Autodesk Inventor part; units mm, degrees
(part 3 of 3)
sketch "Sketch11" plane through (0, 7, 0) normal (0, 1, 0) x (1, 0, 0)
  circle A0 centre (-224.5, -119.5) radius 26.5 projected
  circle A1 centre (-224.5, -56.5) radius 26.5 projected
  circle A2 centre (-224.5, 11.5) radius 26.5 projected
  circle A3 centre (-224.5, 74.5) radius 26.5 projected
  circle A4 centre (-161.5, 74.5) radius 26.5 projected
  circle A5 centre (-161.5, 11.5) radius 26.5 projected
  circle A6 centre (-161.5, -56.5) radius 26.5 projected
  circle A7 centre (-161.5, -119.5) radius 26.5 projected
  circle A8 centre (-98.5, -119.5) radius 26.5 projected
  circle A9 centre (-98.5, -56.5) radius 26.5 projected
  circle A10 centre (-98.5, 11.5) radius 26.5 projected
  circle A11 centre (-98.5, 74.5) radius 26.5 projected
  circle A12 centre (-35.5, 74.5) radius 26.5 projected
  circle A13 centre (-35.5, 11.5) radius 26.5 projected
  circle A14 centre (-35.5, -56.5) radius 26.5 projected
  circle A15 centre (-35.5, -119.5) radius 26.5 projected
  arc A16 (31, 27.5) -> (31, -27.5) centre (31, 0) ccw projected
  line L0 (-234.5, -129.5) -> (-214.5, -129.5)
  line L1 (-214.5, -129.5) -> (-214.5, -119.5)
  line L2 (-214.5, -119.5) -> (-234.5, -119.5)
  line L3 (-234.5, -119.5) -> (-234.5, -129.5)
  line L4 (-232, -117.5) -> (-217, -117.5)
  line L5 (-217, -117.5) -> (-217, -114.5)
  line L6 (-217, -114.5) -> (-232, -114.5)
  line L7 (-232, -114.5) -> (-232, -117.5)
  line L8 (143.5, 108.65) -> (143.5, 89) projected
  line L9 (143.5, 89) -> (161.64, 89) projected
  line L10 (161.64, 89) -> (161.64, 82) projected
  line L11 (161.64, 82) -> (125.72, 82) projected
  line L12 (125.72, 82) -> (125.72, 89) projected
  line L13 (125.72, 89) -> (140.5, 89) projected
  line L14 (140.5, 89) -> (140.5, 108.65) projected
  line L15 (140.5, 108.65) -> (143.5, 108.65) projected
  line L16 (275.65, -125) -> (255.35, -125) projected
  line L17 (255.35, -125) -> (255.35, -122) projected
  line L18 (255.35, -122) -> (275.65, -122) projected
  line L19 (275.65, -122) -> (275.65, -125) projected
  line L20 (320.65, 122) -> (300.35, 122) projected
  line L21 (300.35, 122) -> (300.35, 125) projected
  line L22 (300.35, 125) -> (320.65, 125) projected
  line L23 (320.65, 125) -> (320.65, 122) projected
  line L24 (275.65, 122) -> (255.35, 122) projected
  line L25 (255.35, 122) -> (255.35, 125) projected
  line L26 (255.35, 125) -> (275.65, 125) projected
  line L27 (275.65, 125) -> (275.65, 122) projected
  line L28 (143.5, -108.65) -> (140.5, -108.65) projected
  line L29 (140.5, -108.65) -> (140.5, -88.35) projected
  line L30 (140.5, -88.35) -> (143.5, -88.35) projected
  line L31 (143.5, -88.35) -> (143.5, -108.65) projected
  line L32 (320.65, -122) -> (320.65, -125) projected
  line L33 (320.65, -125) -> (300.35, -125) projected
  line L34 (300.35, -125) -> (300.35, -122) projected
  line L35 (300.35, -122) -> (320.65, -122) projected
  line L36 (230.65, -122) -> (230.65, -125) projected
  line L37 (230.65, -125) -> (210.35, -125) projected
  line L38 (210.35, -125) -> (210.35, -122) projected
  line L39 (210.35, -122) -> (230.65, -122) projected
  line L40 (185.65, 122) -> (165.35, 122) projected
  line L41 (165.35, 122) -> (165.35, 125) projected
  line L42 (165.35, 125) -> (185.65, 125) projected
  line L43 (185.65, 125) -> (185.65, 122) projected
  line L44 (337.5, 88.35) -> (337.5, 108.65) projected
  line L45 (337.5, 108.65) -> (340.5, 108.65) projected
  line L46 (340.5, 108.65) -> (340.5, 88.35) projected
  line L47 (340.5, 88.35) -> (337.5, 88.35) projected
  line L48 (230.65, 122) -> (210.35, 122) projected
  line L49 (210.35, 122) -> (210.35, 125) projected
  line L50 (210.35, 125) -> (230.65, 125) projected
  line L51 (230.65, 125) -> (230.65, 122) projected
  line L52 (185.65, -125) -> (165.35, -125) projected
  line L53 (165.35, -125) -> (165.35, -122) projected
  line L54 (165.35, -122) -> (185.65, -122) projected
  line L55 (185.65, -122) -> (185.65, -125) projected
  line L56 (337.5, -108.65) -> (337.5, -88.35) projected
  line L57 (337.5, -88.35) -> (340.5, -88.35) projected
  line L58 (340.5, -88.35) -> (340.5, -108.65) projected
  line L59 (340.5, -108.65) -> (337.5, -108.65) projected
  line L60 (305.32, -182) -> (305.32, -189) projected
  line L61 (305.32, -189) -> (269.4, -189) projected
  line L62 (269.4, -189) -> (269.4, -182) projected
  line L63 (269.4, -182) -> (305.32, -182) projected
  line L64 (17.96, -182) -> (17.96, -189) projected
  line L65 (17.96, -189) -> (-17.96, -189) projected
  line L66 (-17.96, -189) -> (-17.96, -182) projected
  line L67 (-17.96, -182) -> (17.96, -182) projected
  line L68 (-269.4, -182) -> (-269.4, -189) projected
  line L69 (-269.4, -189) -> (-305.32, -189) projected
  line L70 (-305.32, -189) -> (-305.32, -182) projected
  line L71 (-305.32, -182) -> (-269.4, -182) projected
  line L72 (377.16, 89) -> (377.16, 82) projected
  line L73 (377.16, 82) -> (341.24, 82) projected
  line L74 (341.24, 82) -> (341.24, 89) projected
  line L75 (341.24, 89) -> (377.16, 89) projected
  line L76 (89.8, 89) -> (89.8, 82) projected
  line L77 (89.8, 82) -> (53.88, 82) projected
  line L78 (53.88, 82) -> (53.88, 89) projected
  line L79 (53.88, 89) -> (89.8, 89) projected
  line L80 (-197.56, 89) -> (-197.56, 82) projected
  line L81 (-197.56, 82) -> (-233.48, 82) projected
  line L82 (-233.48, 82) -> (-233.48, 89) projected
  line L83 (-233.48, 89) -> (-197.56, 89) projected
  line L84 (-449, 82) -> (-449, 89) projected
  line L85 (-449, 89) -> (-413.08, 89) projected
  line L86 (-413.08, 89) -> (-413.08, 82) projected
  line L87 (-413.08, 82) -> (-449, 82) projected
  line L88 (-125.72, 89) -> (-125.72, 82) projected
  line L89 (-125.72, 82) -> (-161.64, 82) projected
  line L90 (-161.64, 82) -> (-161.64, 89) projected
  line L91 (-161.64, 89) -> (-125.72, 89) projected
  line L92 (449, 89) -> (449, 82) projected
  line L93 (449, 82) -> (413.08, 82) projected
  line L94 (413.08, 82) -> (413.08, 89) projected
  line L95 (413.08, 89) -> (449, 89) projected
  line L96 (-197.56, -182) -> (-197.56, -189) projected
  line L97 (-197.56, -189) -> (-233.48, -189) projected
  line L98 (-233.48, -189) -> (-233.48, -182) projected
  line L99 (-233.48, -182) -> (-197.56, -182) projected
  line L100 (89.8, -182) -> (89.8, -189) projected
  line L101 (89.8, -189) -> (53.88, -189) projected
  line L102 (53.88, -189) -> (53.88, -182) projected
  line L103 (53.88, -182) -> (89.8, -182) projected
  line L104 (377.16, -182) -> (377.16, -189) projected
  line L105 (377.16, -189) -> (341.24, -189) projected
  line L106 (341.24, -189) -> (341.24, -182) projected
  line L107 (341.24, -182) -> (377.16, -182) projected
  line L108 (233.48, -182) -> (233.48, -189) projected
  line L109 (233.48, -189) -> (197.56, -189) projected
  line L110 (197.56, -189) -> (197.56, -182) projected
  line L111 (197.56, -182) -> (233.48, -182) projected
  line L112 (-53.88, -182) -> (-53.88, -189) projected
  line L113 (-53.88, -189) -> (-89.8, -189) projected
  line L114 (-89.8, -189) -> (-89.8, -182) projected
  line L115 (-89.8, -182) -> (-53.88, -182) projected
  line L116 (-341.24, -182) -> (-341.24, -189) projected
  line L117 (-341.24, -189) -> (-377.16, -189) projected
  line L118 (-377.16, -189) -> (-377.16, -182) projected
  line L119 (-377.16, -182) -> (-341.24, -182) projected
  line L120 (305.32, 89) -> (305.32, 82) projected
  line L121 (305.32, 82) -> (269.4, 82) projected
  line L122 (269.4, 82) -> (269.4, 89) projected
  line L123 (269.4, 89) -> (305.32, 89) projected
  line L124 (17.96, 89) -> (17.96, 82) projected
  line L125 (17.96, 82) -> (-17.96, 82) projected
  line L126 (-17.96, 82) -> (-17.96, 89) projected
  line L127 (-17.96, 89) -> (17.96, 89) projected
  line L128 (-269.4, 89) -> (-269.4, 82) projected
  line L129 (-269.4, 82) -> (-305.32, 82) projected
  line L130 (-305.32, 82) -> (-305.32, 89) projected
  line L131 (-305.32, 89) -> (-269.4, 89) projected
  line L132 (-341.24, 89) -> (-341.24, 82) projected
  line L133 (-341.24, 82) -> (-377.16, 82) projected
  line L134 (-377.16, 82) -> (-377.16, 89) projected
  line L135 (-377.16, 89) -> (-341.24, 89) projected
  line L136 (-53.88, 89) -> (-53.88, 82) projected
  line L137 (-53.88, 82) -> (-89.8, 82) projected
  line L138 (-89.8, 82) -> (-89.8, 89) projected
  line L139 (-89.8, 89) -> (-53.88, 89) projected
  line L140 (233.48, 89) -> (233.48, 82) projected
  line L141 (233.48, 82) -> (197.56, 82) projected
  line L142 (197.56, 82) -> (197.56, 89) projected
  line L143 (197.56, 89) -> (233.48, 89) projected
  line L144 (-449, -189) -> (-449, -182) projected
  line L145 (-449, -182) -> (-413.08, -182) projected
  line L146 (-413.08, -182) -> (-413.08, -189) projected
  line L147 (-413.08, -189) -> (-449, -189) projected
  line L148 (-125.72, -182) -> (-125.72, -189) projected
  line L149 (-125.72, -189) -> (-161.64, -189) projected
  line L150 (-161.64, -189) -> (-161.64, -182) projected
  line L151 (-161.64, -182) -> (-125.72, -182) projected
  line L152 (161.64, -182) -> (161.64, -189) projected
  line L153 (161.64, -189) -> (125.72, -189) projected
  line L154 (125.72, -189) -> (125.72, -182) projected
  line L155 (125.72, -182) -> (161.64, -182) projected
  line L156 (449, -182) -> (449, -189) projected
  line L157 (449, -189) -> (413.08, -189) projected
  line L158 (413.08, -189) -> (413.08, -182) projected
  line L159 (413.08, -182) -> (449, -182) projected
  circle A17 centre (11, -29.5) radius 2.5 projected
  circle A18 centre (36.5, -281.7169) radius 1.575 projected
  circle A19 centre (-51, -301.5) radius 1 projected
  circle A20 centre (-145.2893, -322.9439) radius 1.75 projected
  line L160 (-289.653, -348.9) -> (-289.653, -353.4) projected
  line L161 (-289.653, -353.4) -> (-294.103, -353.4) projected
  arc A21 (-294.103, -348.9) -> (-294.103, -353.4) centre (-294.103, -351.15) ccw projected
  line L162 (-294.103, -348.9) -> (-289.653, -348.9) projected
  line L163 (-264.153, -353.4) -> (-264.153, -348.9) projected
  line L164 (-264.153, -348.9) -> (-259.703, -348.9) projected
  arc A22 (-259.703, -353.4) -> (-259.703, -348.9) centre (-259.703, -351.15) ccw projected
  line L165 (-259.703, -353.4) -> (-264.153, -353.4) projected
  circle A23 centre (-107.9098, -322.9439) radius 1.75 projected
  circle A24 centre (8.08, -301.5) radius 1 projected
  circle A25 centre (126, -281.2169) radius 1.6 projected
  circle A26 centre (256, 65.5) radius 2 projected
  circle A27 centre (11, 29.5) radius 2.5 projected
  circle A28 centre (35.5, -371.2169) radius 1.575 projected
  circle A29 centre (-51, -374.5) radius 1 projected
  circle A30 centre (-145.2893, -359.6857) radius 1.75 projected
  line L166 (-385.653, -353.4) -> (-385.653, -348.9) projected
  line L167 (-385.653, -348.9) -> (-381.203, -348.9) projected
  arc A31 (-381.203, -353.4) -> (-381.203, -348.9) centre (-381.203, -351.15) ccw projected
  line L168 (-381.203, -353.4) -> (-385.653, -353.4) projected
  line L169 (-168.153, -353.4) -> (-172.603, -353.4) projected
  arc A32 (-172.603, -348.9) -> (-172.603, -353.4) centre (-172.603, -351.15) ccw projected
  line L170 (-172.603, -348.9) -> (-168.153, -348.9) projected
  line L171 (-168.153, -348.9) -> (-168.153, -353.4) projected
  circle A33 centre (-107.9098, -359.6857) radius 1.75 projected
  circle A34 centre (8.08, -374.5) radius 1 projected
  circle A35 centre (127, -371.2169) radius 1.575 projected
  circle A36 centre (276, 65.5) radius 2 projected
  arc A37 (-449, -412) -> (-442, -419) centre (-442, -412) ccw projected
  line L172 (-442, -419) -> (-407.85, -419) projected
  line L173 (-407.85, -419) -> (-407.85, -426) projected
  line L174 (-407.85, -426) -> (-360.15, -426) projected
  line L175 (-360.15, -426) -> (-360.15, -419) projected
  line L176 (-360.15, -419) -> (-311.85, -419) projected
  line L177 (-311.85, -419) -> (-311.85, -426) projected
  line L178 (-311.85, -426) -> (-264.15, -426) projected
  line L179 (-264.15, -426) -> (-264.15, -419) projected
  line L180 (-264.15, -419) -> (-215.85, -419) projected
  line L181 (-215.85, -419) -> (-215.85, -426) projected
  line L182 (-215.85, -426) -> (-168.15, -426) projected
  line L183 (-168.15, -426) -> (-168.15, -419) projected
  line L184 (-168.15, -419) -> (-119.85, -419) projected
  line L185 (-119.85, -419) -> (-119.85, -426) projected
  line L186 (-119.85, -426) -> (-72.15, -426) projected
  line L187 (-72.15, -426) -> (-72.15, -419) projected
  line L188 (-72.15, -419) -> (-23.85, -419) projected
  line L189 (-23.85, -419) -> (-23.85, -426) projected
  line L190 (-23.85, -426) -> (23.85, -426) projected
  line L191 (23.85, -426) -> (23.85, -419) projected
  line L192 (23.85, -419) -> (72.15, -419) projected
  line L193 (72.15, -419) -> (72.15, -426) projected
  line L194 (72.15, -426) -> (119.85, -426) projected
  line L195 (119.85, -426) -> (119.85, -419) projected
  line L196 (119.85, -419) -> (168.15, -419) projected
  line L197 (168.15, -419) -> (168.15, -426) projected
  line L198 (168.15, -426) -> (215.85, -426) projected
  line L199 (215.85, -426) -> (215.85, -419) projected
  line L200 (215.85, -419) -> (264.15, -419) projected
  line L201 (264.15, -419) -> (264.15, -426) projected
  line L202 (264.15, -426) -> (311.85, -426) projected
  line L203 (311.85, -426) -> (311.85, -419) projected
  line L204 (311.85, -419) -> (360.15, -419) projected
  line L205 (360.15, -419) -> (360.15, -426) projected
  line L206 (360.15, -426) -> (407.85, -426) projected
  line L207 (407.85, -426) -> (407.85, -419) projected
  line L208 (407.85, -419) -> (442, -419) projected
  arc A38 (442, -419) -> (449, -412) centre (442, -412) ccw projected
  line L209 (449, -412) -> (449, -399.77) projected
  line L210 (449, -399.77) -> (456, -399.77) projected
  line L211 (456, -399.77) -> (456, -373.99) projected
  line L212 (456, -373.99) -> (449, -373.99) projected
  line L213 (449, -373.99) -> (449, -347.61) projected
  line L214 (449, -347.61) -> (456, -347.61) projected
  line L215 (456, -347.61) -> (456, -321.83) projected
  line L216 (456, -321.83) -> (449, -321.83) projected
  line L217 (449, -321.83) -> (449, -295.45) projected
  line L218 (449, -295.45) -> (456, -295.45) projected
  line L219 (456, -295.45) -> (456, -269.67) projected
  line L220 (456, -269.67) -> (449, -269.67) projected
  line L221 (449, -269.67) -> (449, -243.29) projected
  line L222 (449, -243.29) -> (456, -243.29) projected
  line L223 (456, -243.29) -> (456, -217.51) projected
  line L224 (456, -217.51) -> (449, -217.51) projected
  line L225 (449, -217.51) -> (449, -191.13) projected
  line L226 (449, -191.13) -> (456, -191.13) projected
  line L227 (456, -191.13) -> (456, -165.35) projected
  line L228 (456, -165.35) -> (449, -165.35) projected
  line L229 (449, -165.35) -> (449, -138.97) projected
  line L230 (449, -138.97) -> (456, -138.97) projected
  line L231 (456, -138.97) -> (456, -113.19) projected
  line L232 (456, -113.19) -> (449, -113.19) projected
  line L233 (449, -113.19) -> (449, -86.81) projected
  line L234 (449, -86.81) -> (456, -86.81) projected
  line L235 (456, -86.81) -> (456, -61.03) projected
  line L236 (456, -61.03) -> (449, -61.03) projected
  line L237 (449, -61.03) -> (449, -34.65) projected
  line L238 (449, -34.65) -> (456, -34.65) projected
  line L239 (456, -34.65) -> (456, -8.87) projected
  line L240 (456, -8.87) -> (449, -8.87) projected
  line L241 (449, -8.87) -> (449, 17.51) projected
  line L242 (449, 17.51) -> (456, 17.51) projected
  line L243 (456, 17.51) -> (456, 43.29) projected
  line L244 (456, 43.29) -> (449, 43.29) projected
  line L245 (449, 43.29) -> (449, 69.67) projected
  line L246 (449, 69.67) -> (456, 69.67) projected
  line L247 (456, 69.67) -> (456, 95.45) projected
  line L248 (456, 95.45) -> (449, 95.45) projected
  line L249 (449, 95.45) -> (449, 121.83) projected
  line L250 (449, 121.83) -> (456, 121.83) projected
  line L251 (456, 121.83) -> (456, 147.61) projected
  line L252 (456, 147.61) -> (449, 147.61) projected
  line L253 (449, 147.61) -> (449, 173.99) projected
  line L254 (449, 173.99) -> (456, 173.99) projected
  line L255 (456, 173.99) -> (456, 199.77) projected
  line L256 (456, 199.77) -> (449, 199.77) projected
  line L257 (449, 199.77) -> (449, 212) projected
  arc A39 (449, 212) -> (442, 219) centre (442, 212) ccw projected
  line L258 (442, 219) -> (407.85, 219) projected
  line L259 (407.85, 219) -> (407.85, 226) projected
  line L260 (407.85, 226) -> (360.15, 226) projected
  line L261 (360.15, 226) -> (360.15, 219) projected
  line L262 (360.15, 219) -> (311.85, 219) projected
  line L263 (311.85, 219) -> (311.85, 226) projected
  line L264 (311.85, 226) -> (264.15, 226) projected
  line L265 (264.15, 226) -> (264.15, 219) projected
  line L266 (264.15, 219) -> (215.85, 219) projected
  line L267 (215.85, 219) -> (215.85, 226) projected
  line L268 (215.85, 226) -> (168.15, 226) projected
  line L269 (168.15, 226) -> (168.15, 219) projected
  line L270 (168.15, 219) -> (119.85, 219) projected
  line L271 (119.85, 219) -> (119.85, 226) projected
  line L272 (119.85, 226) -> (72.15, 226) projected
  line L273 (72.15, 226) -> (72.15, 219) projected
  line L274 (72.15, 219) -> (23.85, 219) projected
  line L275 (23.85, 219) -> (23.85, 226) projected
  line L276 (23.85, 226) -> (-23.85, 226) projected
  line L277 (-23.85, 226) -> (-23.85, 219) projected
  line L278 (-23.85, 219) -> (-72.15, 219) projected
  line L279 (-72.15, 219) -> (-72.15, 226) projected
  line L280 (-72.15, 226) -> (-119.85, 226) projected
  line L281 (-119.85, 226) -> (-119.85, 219) projected
  line L282 (-119.85, 219) -> (-168.15, 219) projected
  line L283 (-168.15, 219) -> (-168.15, 226) projected
  line L284 (-168.15, 226) -> (-215.85, 226) projected
  line L285 (-215.85, 226) -> (-215.85, 219) projected
  line L286 (-215.85, 219) -> (-264.15, 219) projected
  line L287 (-264.15, 219) -> (-264.15, 226) projected
  line L288 (-264.15, 226) -> (-311.85, 226) projected
  line L289 (-311.85, 226) -> (-311.85, 219) projected
  line L290 (-311.85, 219) -> (-360.15, 219) projected
  line L291 (-360.15, 219) -> (-360.15, 226) projected
  line L292 (-360.15, 226) -> (-407.85, 226) projected
  line L293 (-407.85, 226) -> (-407.85, 219) projected
  line L294 (-407.85, 219) -> (-442, 219) projected
  arc A40 (-442, 219) -> (-449, 212) centre (-442, 212) ccw projected
  line L295 (-449, 212) -> (-449, 199.77) projected
  line L296 (-449, 199.77) -> (-456, 199.77) projected
  line L297 (-456, 199.77) -> (-456, 173.99) projected
  line L298 (-456, 173.99) -> (-449, 173.99) projected
  line L299 (-449, 173.99) -> (-449, 147.61) projected
  line L300 (-449, 147.61) -> (-456, 147.61) projected
  line L301 (-456, 147.61) -> (-456, 121.83) projected
  line L302 (-456, 121.83) -> (-449, 121.83) projected
  line L303 (-449, 121.83) -> (-449, 95.45) projected
  line L304 (-449, 95.45) -> (-456, 95.45) projected
  line L305 (-456, 95.45) -> (-456, 69.67) projected
  line L306 (-456, 69.67) -> (-449, 69.67) projected
  line L307 (-449, 69.67) -> (-449, 43.29) projected
  line L308 (-449, 43.29) -> (-456, 43.29) projected
  line L309 (-456, 43.29) -> (-456, 17.51) projected
  line L310 (-456, 17.51) -> (-449, 17.51) projected
  line L311 (-449, 17.51) -> (-449, -8.87) projected
  line L312 (-449, -8.87) -> (-456, -8.87) projected
  line L313 (-456, -8.87) -> (-456, -34.65) projected
  line L314 (-456, -34.65) -> (-449, -34.65) projected
  line L315 (-449, -34.65) -> (-449, -61.03) projected
  line L316 (-449, -61.03) -> (-456, -61.03) projected
  line L317 (-456, -61.03) -> (-456, -86.81) projected
  line L318 (-456, -86.81) -> (-449, -86.81) projected
  line L319 (-449, -86.81) -> (-449, -113.19) projected
  line L320 (-449, -113.19) -> (-456, -113.19) projected
  line L321 (-456, -113.19) -> (-456, -138.97) projected
  line L322 (-456, -138.97) -> (-449, -138.97) projected
  line L323 (-449, -138.97) -> (-449, -165.35) projected
  line L324 (-449, -165.35) -> (-456, -165.35) projected
  line L325 (-456, -165.35) -> (-456, -191.13) projected
  line L326 (-456, -191.13) -> (-449, -191.13) projected
  line L327 (-449, -191.13) -> (-449, -217.51) projected
  line L328 (-449, -217.51) -> (-456, -217.51) projected
  line L329 (-456, -217.51) -> (-456, -243.29) projected
  line L330 (-456, -243.29) -> (-449, -243.29) projected
  line L331 (-449, -243.29) -> (-449, -269.67) projected
  line L332 (-449, -269.67) -> (-456, -269.67) projected
  line L333 (-456, -269.67) -> (-456, -295.45) projected
  line L334 (-456, -295.45) -> (-449, -295.45) projected
  line L335 (-449, -295.45) -> (-449, -321.83) projected
  line L336 (-449, -321.83) -> (-456, -321.83) projected
  line L337 (-456, -321.83) -> (-456, -347.61) projected
  line L338 (-456, -347.61) -> (-449, -347.61) projected
  line L339 (-449, -347.61) -> (-449, -373.99) projected
  line L340 (-449, -373.99) -> (-456, -373.99) projected
  line L341 (-456, -373.99) -> (-456, -399.77) projected
  line L342 (-456, -399.77) -> (-449, -399.77) projected
  line L343 (-449, -399.77) -> (-449, -412) projected
  line L344 (-376, -283.5) -> (-76, -283.5) projected
  arc A41 (-76, -308.5) -> (-76, -283.5) centre (-76, -296) ccw projected
  line L345 (-76, -308.5) -> (-376, -308.5) projected
  arc A42 (-376, -283.5) -> (-376, -308.5) centre (-376, -296) ccw projected
  line L346 (176.5, -286) -> (176.5, -366) projected
  arc A43 (151.5, -366) -> (176.5, -366) centre (164, -366) ccw projected
  line L347 (151.5, -366) -> (151.5, -286) projected
  arc A44 (176.5, -286) -> (151.5, -286) centre (164, -286) ccw projected
  line L348 (105, -23) -> (105, 23) projected
  arc A45 (107, 25) -> (105, 23) centre (107, 23) ccw projected
  line L349 (107, 25) -> (266, 25) projected
  arc A46 (268, 23) -> (266, 25) centre (266, 23) ccw projected
  line L350 (268, 23) -> (268, -23) projected
  arc A47 (266, -25) -> (268, -23) centre (266, -23) ccw projected
  line L351 (266, -25) -> (107, -25) projected
  arc A48 (105, -23) -> (107, -25) centre (107, -23) ccw projected
  circle A49 centre (354.8, 16) radius 2.9 projected
  circle A50 centre (354.8, -16) radius 2.9 projected
  line L352 (201, -276) -> (204, -276) projected
  line L353 (204, -276) -> (204, -296) projected
  line L354 (204, -296) -> (201, -296) projected
  line L355 (201, -296) -> (201, -276) projected
  line L356 (-426, -316) -> (-423, -316) projected
  line L357 (-423, -316) -> (-423, -336) projected
  line L358 (-423, -336) -> (-426, -336) projected
  line L359 (-426, -336) -> (-426, -316) projected
  line L360 (9, -396) -> (9, -393) projected
  line L361 (9, -393) -> (57, -393) projected
  line L362 (57, -393) -> (57, -396) projected
  line L363 (57, -396) -> (9, -396) projected
  line L364 (-39, -256) -> (-39, -259) projected
  line L365 (-39, -259) -> (-87, -259) projected
  line L366 (-87, -259) -> (-87, -256) projected
  line L367 (-87, -256) -> (-39, -256) projected
  circle A51 centre (-67, 43) radius 2.5 projected
  circle A52 centre (-130, 43) radius 2.5 projected
  line L368 (51.5, 68) -> (46.5, 68) projected
  line L369 (46.5, 68) -> (46.5, 71) projected
  line L370 (46.5, 71) -> (51.5, 71) projected
  line L371 (51.5, 71) -> (51.5, 68) projected
  line L372 (6, 53) -> (3, 53) projected
  line L373 (3, 53) -> (3, 63) projected
  line L374 (3, 63) -> (6, 63) projected
  line L375 (6, 63) -> (6, 53) projected
  line L376 (56.25, -48) -> (46.25, -48) projected
  line L377 (46.25, -48) -> (46.25, -45) projected
  line L378 (46.25, -45) -> (56.25, -45) projected
  line L379 (56.25, -45) -> (56.25, -48) projected
  line L380 (46.25, -81) -> (46.25, -78) projected
  line L381 (46.25, -78) -> (56.25, -78) projected
  line L382 (56.25, -78) -> (56.25, -81) projected
  line L383 (56.25, -81) -> (46.25, -81) projected
  line L384 (61, -134.5) -> (61, -119.5) projected
  line L385 (61, -119.5) -> (64, -119.5) projected
  line L386 (64, -119.5) -> (64, -134.5) projected
  line L387 (64, -134.5) -> (61, -134.5) projected
  arc A53 (-406.25, 176) -> (-406, 176.25) centre (-406.25, 176.25) ccw projected
  line L388 (-406.25, 176) -> (-425.75, 176) projected
  arc A54 (-426, 176.25) -> (-425.75, 176) centre (-425.75, 176.25) ccw projected
  line L389 (-426, 176.25) -> (-426, 195.75) projected
  arc A55 (-425.75, 196) -> (-426, 195.75) centre (-425.75, 195.75) ccw projected
  line L390 (-425.75, 196) -> (-406.25, 196) projected
  arc A56 (-406, 195.75) -> (-406.25, 196) centre (-406.25, 195.75) ccw projected
  line L391 (-406, 195.75) -> (-406, 176.25) projected
  line L392 (-25.75, 196) -> (-6.25, 196) projected
  arc A57 (-6, 195.75) -> (-6.25, 196) centre (-6.25, 195.75) ccw projected
  line L393 (-6, 195.75) -> (-6, 176.25) projected
  arc A58 (-6.25, 176) -> (-6, 176.25) centre (-6.25, 176.25) ccw projected
  line L394 (-6.25, 176) -> (-25.75, 176) projected
  arc A59 (-26, 176.25) -> (-25.75, 176) centre (-25.75, 176.25) ccw projected
  line L395 (-26, 176.25) -> (-26, 195.75) projected
  arc A60 (-25.75, 196) -> (-26, 195.75) centre (-25.75, 195.75) ccw projected
  line L396 (5.5, -233.9) -> (2.5, -233.9) projected
  arc A61 (2.5, -228.1) -> (2.5, -233.9) centre (2.5, -231) ccw projected
  line L397 (2.5, -228.1) -> (5.5, -228.1) projected
  arc A62 (5.5, -233.9) -> (5.5, -228.1) centre (5.5, -231) ccw projected
  line L398 (-394.5, 183.1) -> (-397.5, 183.1) projected
  arc A63 (-397.5, 188.9) -> (-397.5, 183.1) centre (-397.5, 186) ccw projected
  line L399 (-397.5, 188.9) -> (-394.5, 188.9) projected
  arc A64 (-394.5, 183.1) -> (-394.5, 188.9) centre (-394.5, 186) ccw projected
  line L400 (-25.75, -221) -> (-6.25, -221) projected
  arc A65 (-6, -221.25) -> (-6.25, -221) centre (-6.25, -221.25) ccw projected
  line L401 (-6, -221.25) -> (-6, -240.75) projected
  arc A66 (-6.25, -241) -> (-6, -240.75) centre (-6.25, -240.75) ccw projected
  line L402 (-6.25, -241) -> (-25.75, -241) projected
  arc A67 (-26, -240.75) -> (-25.75, -241) centre (-25.75, -240.75) ccw projected
  line L403 (-26, -240.75) -> (-26, -221.25) projected
  arc A68 (-25.75, -221) -> (-26, -221.25) centre (-25.75, -221.25) ccw projected
  line L404 (-394.5, -233.9) -> (-397.5, -233.9) projected
  arc A69 (-397.5, -228.1) -> (-397.5, -233.9) centre (-397.5, -231) ccw projected
  line L405 (-397.5, -228.1) -> (-394.5, -228.1) projected
  arc A70 (-394.5, -233.9) -> (-394.5, -228.1) centre (-394.5, -231) ccw projected
  line L406 (296, -196) -> (296.0285, -196) projected
  line L407 (396, -236.2955) -> (396, -276.2955) projected
  line L408 (396, -396) -> (296, -396) projected
  line L409 (296, -396) -> (296, -196) projected
  line L410 (46.25, -142) -> (56.25, -142) projected
  line L411 (56.25, -142) -> (56.25, -145) projected
  line L412 (56.25, -145) -> (46.25, -145) projected
  line L413 (46.25, -145) -> (46.25, -142) projected
  line L414 (61, -70.5) -> (61, -55.5) projected
  line L415 (61, -55.5) -> (64, -55.5) projected
  line L416 (64, -55.5) -> (64, -70.5) projected
  line L417 (64, -70.5) -> (61, -70.5) projected
  arc A71 (49, -110) -> (44, -105) centre (44, -110) ccw projected
  line L418 (49, -110) -> (49, -120) projected
  arc A72 (44, -125) -> (49, -120) centre (44, -120) ccw projected
  line L419 (44, -125) -> (24, -125) projected
  arc A73 (19, -120) -> (24, -125) centre (24, -120) ccw projected
  line L420 (19, -120) -> (19, -110) projected
  arc A74 (24, -105) -> (19, -110) centre (24, -110) ccw projected
  line L421 (24, -105) -> (44, -105) projected
  line L422 (56, 53) -> (56, 63) projected
  line L423 (56, 63) -> (59, 63) projected
  line L424 (59, 63) -> (59, 53) projected
  line L425 (59, 53) -> (56, 53) projected
  line L426 (25, 62) -> (37, 62) projected
  arc A75 (37, 54) -> (37, 62) centre (37, 58) ccw projected
  line L427 (37, 54) -> (25, 54) projected
  arc A76 (25, 62) -> (25, 54) centre (25, 58) ccw projected
  circle A77 centre (-193, 43) radius 2.5 projected
  circle A78 centre (-67, -88) radius 2.5 projected
  line L428 (-135, -256) -> (-135, -259) projected
  line L429 (-135, -259) -> (-183, -259) projected
  line L430 (-183, -259) -> (-183, -256) projected
  line L431 (-183, -256) -> (-135, -256) projected
  line L432 (105, -396) -> (105, -393) projected
  line L433 (105, -393) -> (153, -393) projected
  line L434 (153, -393) -> (153, -396) projected
  line L435 (153, -396) -> (105, -396) projected
  line L436 (-426, -356) -> (-423, -356) projected
  line L437 (-423, -356) -> (-423, -376) projected
  line L438 (-423, -376) -> (-426, -376) projected
  line L439 (-426, -376) -> (-426, -356) projected
  line L440 (201, -316) -> (204, -316) projected
  line L441 (204, -316) -> (204, -336) projected
  line L442 (204, -336) -> (201, -336) projected
  line L443 (201, -336) -> (201, -316) projected
  line L444 (-279, -396) -> (-279, -393) projected
  line L445 (-279, -393) -> (-231, -393) projected
  line L446 (-231, -393) -> (-231, -396) projected
  line L447 (-231, -396) -> (-279, -396) projected
  line L448 (-426, -276) -> (-423, -276) projected
  line L449 (-423, -276) -> (-423, -296) projected
  line L450 (-423, -296) -> (-426, -296) projected
  line L451 (-426, -296) -> (-426, -276) projected
  line L452 (-87, -396) -> (-87, -393) projected
  line L453 (-87, -393) -> (-39, -393) projected
  line L454 (-39, -393) -> (-39, -396) projected
  line L455 (-39, -396) -> (-87, -396) projected
  line L456 (57, -256) -> (57, -259) projected
  line L457 (57, -259) -> (9, -259) projected
  line L458 (9, -259) -> (9, -256) projected
  line L459 (9, -256) -> (57, -256) projected
  line L460 (-327, -256) -> (-327, -259) projected
  line L461 (-327, -259) -> (-375, -259) projected
  line L462 (-375, -259) -> (-375, -256) projected
  line L463 (-375, -256) -> (-327, -256) projected
  circle A79 centre (-130, -88) radius 2.5 projected
  line L464 (46.5, 48) -> (51.5, 48) projected
  line L465 (51.5, 48) -> (51.5, 45) projected
  line L466 (51.5, 45) -> (46.5, 45) projected
  line L467 (46.5, 45) -> (46.5, 48) projected
  line L468 (10.5, 48) -> (15.5, 48) projected
  line L469 (15.5, 48) -> (15.5, 45) projected
  line L470 (15.5, 45) -> (10.5, 45) projected
  line L471 (10.5, 45) -> (10.5, 48) projected
  circle A80 centre (27.09, -53.5) radius 1.25 projected
  line L472 (21.75, -48) -> (11.75, -48) projected
  line L473 (11.75, -48) -> (11.75, -45) projected
  line L474 (11.75, -45) -> (21.75, -45) projected
  line L475 (21.75, -45) -> (21.75, -48) projected
  line L476 (11.75, -81) -> (11.75, -78) projected
  line L477 (11.75, -78) -> (21.75, -78) projected
  line L478 (21.75, -78) -> (21.75, -81) projected
  line L479 (21.75, -81) -> (11.75, -81) projected
  line L480 (7, -119.5) -> (7, -134.5) projected
  line L481 (7, -134.5) -> (4, -134.5) projected
  line L482 (4, -134.5) -> (4, -119.5) projected
  line L483 (4, -119.5) -> (7, -119.5) projected
  line L484 (-425.75, -221) -> (-406.25, -221) projected
  arc A81 (-406, -221.25) -> (-406.25, -221) centre (-406.25, -221.25) ccw projected
  line L485 (-406, -221.25) -> (-406, -240.75) projected
  arc A82 (-406.25, -241) -> (-406, -240.75) centre (-406.25, -240.75) ccw projected
  line L486 (-406.25, -241) -> (-425.75, -241) projected
  arc A83 (-426, -240.75) -> (-425.75, -241) centre (-425.75, -240.75) ccw projected
  line L487 (-426, -240.75) -> (-426, -221.25) projected
  arc A84 (-425.75, -221) -> (-426, -221.25) centre (-425.75, -221.25) ccw projected
  arc A85 (-37.5, 188.9) -> (-37.5, 183.1) centre (-37.5, 186) ccw projected
  line L488 (-37.5, 188.9) -> (-34.5, 188.9) projected
  arc A86 (-34.5, 183.1) -> (-34.5, 188.9) centre (-34.5, 186) ccw projected
  line L489 (-34.5, 183.1) -> (-37.5, 183.1) projected
  arc A87 (-37.5, -228.1) -> (-37.5, -233.9) centre (-37.5, -231) ccw projected
  line L490 (-37.5, -228.1) -> (-34.5, -228.1) projected
  arc A88 (-34.5, -233.9) -> (-34.5, -228.1) centre (-34.5, -231) ccw projected
  line L491 (-34.5, -233.9) -> (-37.5, -233.9) projected
  arc A89 (-437.5, 188.9) -> (-437.5, 183.1) centre (-437.5, 186) ccw projected
  line L492 (-437.5, 188.9) -> (-434.5, 188.9) projected
  arc A90 (-434.5, 183.1) -> (-434.5, 188.9) centre (-434.5, 186) ccw projected
  line L493 (-434.5, 183.1) -> (-437.5, 183.1) projected
  line L494 (5.5, 183.1) -> (2.5, 183.1) projected
  arc A91 (2.5, 188.9) -> (2.5, 183.1) centre (2.5, 186) ccw projected
  line L495 (2.5, 188.9) -> (5.5, 188.9) projected
  arc A92 (5.5, 183.1) -> (5.5, 188.9) centre (5.5, 186) ccw projected
  arc A93 (-437.5, -228.1) -> (-437.5, -233.9) centre (-437.5, -231) ccw projected
  line L496 (-437.5, -228.1) -> (-434.5, -228.1) projected
  arc A94 (-434.5, -233.9) -> (-434.5, -228.1) centre (-434.5, -231) ccw projected
  line L497 (-434.5, -233.9) -> (-437.5, -233.9) projected
  line L498 (11.75, -142) -> (21.75, -142) projected
  line L499 (21.75, -142) -> (21.75, -145) projected
  line L500 (21.75, -145) -> (11.75, -145) projected
  line L501 (11.75, -145) -> (11.75, -142) projected
  line L502 (7, -55.5) -> (7, -70.5) projected
  line L503 (7, -70.5) -> (4, -70.5) projected
  line L504 (4, -70.5) -> (4, -55.5) projected
  line L505 (4, -55.5) -> (7, -55.5) projected
  circle A95 centre (40.91, -53.5) radius 1.25 projected
  line L506 (29, 48) -> (29, 51) projected
  line L507 (29, 51) -> (33, 51) projected
  line L508 (33, 51) -> (33, 48) projected
  line L509 (33, 48) -> (29, 48) projected
  line L510 (15.5, 68) -> (10.5, 68) projected
  line L511 (10.5, 68) -> (10.5, 71) projected
  line L512 (10.5, 71) -> (15.5, 71) projected
  line L513 (15.5, 71) -> (15.5, 68) projected
  circle A96 centre (-193, -88) radius 2.5 projected
  line L514 (-231, -256) -> (-231, -259) projected
  line L515 (-231, -259) -> (-279, -259) projected
  line L516 (-279, -259) -> (-279, -256) projected
  line L517 (-279, -256) -> (-231, -256) projected
  line L518 (153, -256) -> (153, -259) projected
  line L519 (153, -259) -> (105, -259) projected
  line L520 (105, -259) -> (105, -256) projected
  line L521 (105, -256) -> (153, -256) projected
  line L522 (-183, -396) -> (-183, -393) projected
  line L523 (-183, -393) -> (-135, -393) projected
  line L524 (-135, -393) -> (-135, -396) projected
  line L525 (-135, -396) -> (-183, -396) projected
  line L526 (201, -356) -> (204, -356) projected
  line L527 (204, -356) -> (204, -376) projected
  line L528 (204, -376) -> (201, -376) projected
  line L529 (201, -376) -> (201, -356) projected
  line L530 (-375, -396) -> (-375, -393) projected
  line L531 (-375, -393) -> (-327, -393) projected
  line L532 (-327, -393) -> (-327, -396) projected
  line L533 (-327, -396) -> (-375, -396) projected
  line L534 (-217, -54.5) -> (-217, -51.5)
  line L535 (-217, -51.5) -> (-232, -51.5)
  line L536 (-232, -51.5) -> (-232, -54.5)
  line L537 (-232, -54.5) -> (-217, -54.5)
  line L538 (-214.5, -56.5) -> (-234.5, -56.5)
  line L539 (-234.5, -66.5) -> (-214.5, -66.5)
  line L540 (-234.5, -56.5) -> (-234.5, -66.5)
  line L541 (-214.5, -66.5) -> (-214.5, -56.5)
  line L542 (-154, -117.5) -> (-154, -114.5)
  line L543 (-154, -114.5) -> (-169, -114.5)
  line L544 (-169, -114.5) -> (-169, -117.5)
  line L545 (-169, -117.5) -> (-154, -117.5)
  line L546 (-151.5, -119.5) -> (-171.5, -119.5)
  line L547 (-171.5, -129.5) -> (-151.5, -129.5)
  line L548 (-171.5, -119.5) -> (-171.5, -129.5)
  line L549 (-151.5, -129.5) -> (-151.5, -119.5)
  line L550 (-154, -54.5) -> (-154, -51.5)
  line L551 (-154, -51.5) -> (-169, -51.5)
  line L552 (-169, -51.5) -> (-169, -54.5)
  line L553 (-169, -54.5) -> (-154, -54.5)
  line L554 (-151.5, -56.5) -> (-171.5, -56.5)
  line L555 (-171.5, -66.5) -> (-151.5, -66.5)
  line L556 (-171.5, -56.5) -> (-171.5, -66.5)
  line L557 (-151.5, -66.5) -> (-151.5, -56.5)
  line L558 (-91, -117.5) -> (-91, -114.5)
  line L559 (-91, -114.5) -> (-106, -114.5)
  line L560 (-106, -114.5) -> (-106, -117.5)
  line L561 (-106, -117.5) -> (-91, -117.5)
  line L562 (-88.5, -119.5) -> (-108.5, -119.5)
  line L563 (-108.5, -129.5) -> (-88.5, -129.5)
  line L564 (-108.5, -119.5) -> (-108.5, -129.5)
  line L565 (-88.5, -129.5) -> (-88.5, -119.5)
  line L566 (-91, -54.5) -> (-91, -51.5)
  line L567 (-91, -51.5) -> (-106, -51.5)
  line L568 (-106, -51.5) -> (-106, -54.5)
  line L569 (-106, -54.5) -> (-91, -54.5)
  line L570 (-88.5, -56.5) -> (-108.5, -56.5)
  line L571 (-108.5, -66.5) -> (-88.5, -66.5)
  line L572 (-108.5, -56.5) -> (-108.5, -66.5)
  line L573 (-88.5, -66.5) -> (-88.5, -56.5)
  line L574 (-28, -117.5) -> (-28, -114.5)
  line L575 (-28, -114.5) -> (-43, -114.5)
  line L576 (-43, -114.5) -> (-43, -117.5)
  line L577 (-43, -117.5) -> (-28, -117.5)
  line L578 (-25.5, -119.5) -> (-45.5, -119.5)
  line L579 (-45.5, -129.5) -> (-25.5, -129.5)
  line L580 (-45.5, -119.5) -> (-45.5, -129.5)
  line L581 (-25.5, -129.5) -> (-25.5, -119.5)
  line L582 (-28, -54.5) -> (-28, -51.5)
  line L583 (-28, -51.5) -> (-43, -51.5)
  line L584 (-43, -51.5) -> (-43, -54.5)
  line L585 (-43, -54.5) -> (-28, -54.5)
  line L586 (-25.5, -56.5) -> (-45.5, -56.5)
  line L587 (-45.5, -66.5) -> (-25.5, -66.5)
  line L588 (-45.5, -56.5) -> (-45.5, -66.5)
  line L589 (-25.5, -66.5) -> (-25.5, -56.5)
  line L590 (-249, -20) -> (-200, -20) projected
  line L591 (-200, -25) -> (-249, -25) projected
  line L592 (-249, -22.5) -> (-200, -22.5) construction
  line L593 (-249, -20) -> (-249, -25)
  line L594 (-25.5, 1.5) -> (-25.5, 11.5)
  line L595 (-28, 13.5) -> (-28, 16.5)
  line L596 (-43, 13.5) -> (-28, 13.5)
  line L597 (-28, 16.5) -> (-43, 16.5)
  line L598 (-43, 16.5) -> (-43, 13.5)
  line L599 (-45.5, 1.5) -> (-25.5, 1.5)
  line L600 (-25.5, 11.5) -> (-45.5, 11.5)
  line L601 (-45.5, 11.5) -> (-45.5, 1.5)
  line L602 (-43, 79.5) -> (-43, 76.5)
  line L603 (-28, 79.5) -> (-43, 79.5)
  line L604 (-28, 76.5) -> (-28, 79.5)
  line L605 (-43, 76.5) -> (-28, 76.5)
  line L606 (-25.5, 74.5) -> (-45.5, 74.5)
  line L607 (-45.5, 74.5) -> (-45.5, 64.5)
  line L608 (-45.5, 64.5) -> (-25.5, 64.5)
  line L609 (-25.5, 64.5) -> (-25.5, 74.5)
  line L610 (-108.5, 74.5) -> (-108.5, 64.5)
  line L611 (-106, 79.5) -> (-106, 76.5)
  line L612 (-91, 76.5) -> (-91, 79.5)
  line L613 (-91, 79.5) -> (-106, 79.5)
  line L614 (-108.5, 64.5) -> (-88.5, 64.5)
  line L615 (-88.5, 64.5) -> (-88.5, 74.5)
  line L616 (-88.5, 74.5) -> (-108.5, 74.5)
  line L617 (-106, 76.5) -> (-91, 76.5)
  line L618 (-88.5, 1.5) -> (-88.5, 11.5)
  line L619 (-91, 13.5) -> (-91, 16.5)
  line L620 (-106, 13.5) -> (-91, 13.5)
  line L621 (-108.5, 11.5) -> (-108.5, 1.5)
  line L622 (-88.5, 11.5) -> (-108.5, 11.5)
  line L623 (-106, 16.5) -> (-106, 13.5)
  line L624 (-91, 16.5) -> (-106, 16.5)
  line L625 (-108.5, 1.5) -> (-88.5, 1.5)
  line L626 (-151.5, 64.5) -> (-151.5, 74.5)
  line L627 (-154, 76.5) -> (-154, 79.5)
  line L628 (-154, 79.5) -> (-169, 79.5)
  line L629 (-169, 79.5) -> (-169, 76.5)
  line L630 (-169, 76.5) -> (-154, 76.5)
  line L631 (-151.5, 74.5) -> (-171.5, 74.5)
  line L632 (-171.5, 64.5) -> (-151.5, 64.5)
  line L633 (-171.5, 74.5) -> (-171.5, 64.5)
  line L634 (-171.5, 11.5) -> (-171.5, 1.5)
  line L635 (-169, 16.5) -> (-169, 13.5)
  line L636 (-171.5, 1.5) -> (-151.5, 1.5)
  line L637 (-169, 13.5) -> (-154, 13.5)
  line L638 (-151.5, 11.5) -> (-171.5, 11.5)
  line L639 (-154, 16.5) -> (-169, 16.5)
  line L640 (-151.5, 1.5) -> (-151.5, 11.5)
  line L641 (-154, 13.5) -> (-154, 16.5)
  line L642 (-217, 16.5) -> (-232, 16.5)
  line L643 (-232, 13.5) -> (-217, 13.5)
  line L644 (-232, 16.5) -> (-232, 13.5)
  line L645 (-214.5, 11.5) -> (-234.5, 11.5)
  line L646 (-234.5, 11.5) -> (-234.5, 1.5)
  line L647 (-234.5, 1.5) -> (-214.5, 1.5)
  line L648 (-214.5, 1.5) -> (-214.5, 11.5)
  line L649 (-217, 13.5) -> (-217, 16.5)
  line L650 (-234.5, 64.5) -> (-214.5, 64.5)
  line L651 (-214.5, 74.5) -> (-234.5, 74.5)
  line L652 (-214.5, 64.5) -> (-214.5, 74.5)
  line L653 (-234.5, 74.5) -> (-234.5, 64.5)
  line L654 (-232, 76.5) -> (-217, 76.5)
  line L655 (-217, 76.5) -> (-217, 79.5)
  line L656 (-217, 79.5) -> (-232, 79.5)
  line L657 (-232, 79.5) -> (-232, 76.5)
  line L658 (13.5, -7.5) -> (16.5, -7.5)
  line L659 (16.5, -7.5) -> (16.5, 7.5)
  line L660 (16.5, 7.5) -> (13.5, 7.5)
  line L661 (13.5, 7.5) -> (13.5, -7.5)
  line L662 (18.5, 10) -> (28.5, 10)
  line L663 (28.5, 10) -> (28.5, -10)
  line L664 (28.5, -10) -> (18.5, -10)
  line L665 (18.5, -10) -> (18.5, 10)
  line L666 (296.0285, -196) -> (296.0285, -236.2955) projected
  line L667 (296.0285, -236.2955) -> (299, -236.2955) projected
  line L668 (299, -236.2955) -> (299, -276.2955) projected
  line L669 (299, -276.2955) -> (296.0285, -276.2955) projected
  line L670 (296.0285, -276.2955) -> (296.0285, -316.5955) projected
  line L671 (296.0285, -316.5955) -> (299, -316.5955) projected
  line L672 (299, -316.5955) -> (299, -356.5955) projected
  line L673 (299, -356.5955) -> (296.0285, -356.5955) projected
  line L674 (296.0285, -356.5955) -> (296.0285, -395.9955) projected
  line L675 (296.0285, -395.9955) -> (299.0285, -395.9955) projected
  line L676 (299.0285, -395.9955) -> (299.0285, -393) projected
  line L677 (299.0285, -393) -> (312.7285, -393) projected
  line L678 (312.7285, -393) -> (312.7285, -395.9955) projected
  line L679 (312.7285, -395.9955) -> (353.0285, -395.9955) projected
  line L680 (353.0285, -395.9955) -> (353.0285, -393) projected
  line L681 (353.0285, -393) -> (393, -393) projected
  line L682 (393, -393) -> (393, -199) projected
  line L683 (393, -199) -> (299.0285, -199) projected
  line L684 (299.0285, -199) -> (299.0285, -196) projected
  line L685 (299.0285, -196) -> (312.7285, -196) projected
  line L686 (312.7285, -196) -> (312.7285, -198.9955) projected
  line L687 (312.7285, -198.9955) -> (353.0285, -198.9955) projected
  line L688 (353.0285, -198.9955) -> (353.0285, -196) projected
  line L689 (353.0285, -196) -> (393.0285, -196) projected
  line L690 (393.0285, -196) -> (393.0285, -236.2955) projected
  line L691 (393.0285, -236.2955) -> (396, -236.2955) projected
  line L692 (396, -276.2955) -> (393.0285, -276.2955) projected
  line L693 (393.0285, -276.2955) -> (393.0285, -316.5955) projected
  line L694 (393.0285, -316.5955) -> (396, -316.5955) projected
  line L695 (396, -316.5955) -> (396, -356.5955) projected
  line L696 (396, -356.5955) -> (393.0285, -356.5955) projected
  line L697 (393.0285, -356.5955) -> (393.0285, -395.9955) projected
  line L698 (393.0285, -395.9955) -> (396, -395.9955) projected
  line L699 (396, -395.9955) -> (396, -396) projected
  point P0 (0, 0)
  point P1 (-224.5, -117.5)
  point P2 (-224.5, -54.5)
  point P3 (-161.5, -117.5)
  point P4 (-161.5, -119.5)
  point P5 (-161.5, -54.5)
  point P6 (-161.5, -56.5)
  point P7 (-98.5, -117.5)
  point P8 (-98.5, -119.5)
  point P9 (-98.5, -54.5)
  point P10 (-98.5, -56.5)
  point P11 (-35.5, -117.5)
  point P12 (-35.5, -119.5)
  point P13 (-35.5, -54.5)
  point P14 (-35.5, -56.5)
  point P15 (-35.5, 11.5)
  point P16 (-35.5, 13.5)
  point P17 (-35.5, 76.5)
  point P18 (-35.5, 74.5)
  point P19 (-98.5, 76.5)
  point P20 (-98.5, 74.5)
  point P21 (-98.5, 11.5)
  point P22 (-98.5, 13.5)
  point P23 (-161.5, 76.5)
  point P24 (-161.5, 74.5)
  point P25 (-161.5, 11.5)
  point P26 (-161.5, 13.5)
  point P27 (-224.5, 13.5)
  point P28 (-224.5, 11.5)
  point P29 (-224.5, 74.5)
  point P30 (-224.5, 76.5)
  point P31 (13.5, 0)
  point P32 (3.5, 0)
  point P33 (18.5, 0)
  dimension "d526" = 20
  dimension "d527" = 10
  dimension "d528" = 15
  dimension "d529" = 3
  dimension "d530" = 2
  dimension "d533" = 63
  dimension "d536" = 63
  dimension "d541" = 131
  dimension "d546" = 15
  dimension "d547" = 3
  dimension "d548" = 10
  dimension "d549" = 10
  dimension "d550" = 20
  dimension "d551" = 2
  constraints: 276 end point, 8 parallel, 6 horizontal, 5 midpoint, 5 perpendicular, 4 coincident, 2 horizontal alignment, 2 vertical, 1 point on circle, 1 vertical alignment, 270 other
  measures "d526" distance of L0.start L0.end
  measures "d527" distance of L2.end L0.start
  measures "d528" distance of L4.start L4.end
  measures "d529" distance of L6.end L4.start
  measures "d530" distance between parallel lines of L2 L4
  measures "d533" distance of L5.end L534.end
  measures "d536" distance of L5.end L542.end
  measures "d541" distance of L578.start L594.end
  measures "d546" distance of L658.end L659.end
  measures "d547" distance of L659.end L660.end
  measures "d548" distance from line of point (3.5, 0) L661
  measures "d549" distance of L663.end L664.end
  measures "d550" distance of L662.end L663.end
  measures "d551" distance between parallel lines of L665 L659
extrude "Extrusion12" cut sketch "Sketch11" against normal through all contours L661 L660 L659 L658 | L662 L663 L664 L665
sketch "Sketch12" plane through (0, 7, 0) normal (0, 1, 0) x (1, 0, 0)
  line L0 (0, -73.8417) -> (456, -73.8417)
  line L1 (456, -86.81) -> (456, -61.03) projected
  line L2 (0, -73.8417) -> (456, -73.8417) construction
  circle A0 centre (192.0377, -73.8417) radius 1.6
  circle A1 centre (207.0377, -73.8417) radius 1.6
  point P0 (0, 0)
  dimension "d566" = 3.2
  dimension "d567" = 3.2
  dimension "d568" = 15
  constraints: 4 end point, 3 point on line, 2 centre point, 1 collinear, 1 horizontal
  measures "d566" diameter of A0
  measures "d567" diameter of A1
  measures "d568" distance of A1.centre A0.centre
extrude "Extrusion13" cut sketch "Sketch12" against normal blind 7
sketch "Sketch13" plane through (0, 7, 0) normal (0, 1, 0) x (1, 0, 0)
  line L0 (192.5, -376) -> (189.5, -376) construction
  line L1 (192.5, -373.1) -> (189.5, -373.1)
  line L2 (189.5, -378.9) -> (192.5, -378.9)
  arc A0 (192.5, -378.9) -> (192.5, -373.1) centre (192.5, -376) ccw
  arc A1 (189.5, -373.1) -> (189.5, -378.9) centre (189.5, -376) ccw
  line L3 (201, -376) -> (201, -356) projected
  line L4 (153, -396) -> (105, -396) projected
  line L5 (178.1, -384.5) -> (178.1, -381.5) construction
  line L6 (181, -384.5) -> (181, -381.5)
  line L7 (175.2, -381.5) -> (175.2, -384.5)
  arc A2 (175.2, -384.5) -> (181, -384.5) centre (178.1, -384.5) ccw
  arc A3 (181, -381.5) -> (175.2, -381.5) centre (178.1, -381.5) ccw
  line L8 (105, -393) -> (153, -393) projected
  line L9 (204, -316) -> (204, -336) projected
  line L10 (-426, -336) -> (-426, -316) projected
  line L11 (204, -336) -> (204, -316) projected
  line L12 (204, -326) -> (-426, -326) construction
  line L13 (-135, -396) -> (-183, -396) projected
  line L14 (-183, -256) -> (-135, -256) projected
  line L15 (192.5, -276) -> (189.5, -276) construction
  line L16 (192.5, -278.9) -> (189.5, -278.9)
  line L17 (189.5, -273.1) -> (192.5, -273.1)
  arc A4 (192.5, -278.9) -> (192.5, -273.1) centre (192.5, -276) ccw
  arc A5 (189.5, -273.1) -> (189.5, -278.9) centre (189.5, -276) ccw
  line L18 (178.1, -267.5) -> (178.1, -270.5) construction
  line L19 (181, -267.5) -> (181, -270.5)
  line L20 (175.2, -270.5) -> (175.2, -267.5)
  arc A6 (181, -267.5) -> (175.2, -267.5) centre (178.1, -267.5) ccw
  arc A7 (175.2, -270.5) -> (181, -270.5) centre (178.1, -270.5) ccw
  line L21 (-111, -326) -> (-111, -426) construction
  line L22 (-119.85, -426) -> (-72.15, -426) projected
  line L23 (-414.5, -376) -> (-411.5, -376) construction
  line L24 (-414.5, -373.1) -> (-411.5, -373.1)
  line L25 (-411.5, -378.9) -> (-414.5, -378.9)
  arc A8 (-414.5, -373.1) -> (-414.5, -378.9) centre (-414.5, -376) ccw
  arc A9 (-411.5, -378.9) -> (-411.5, -373.1) centre (-411.5, -376) ccw
  line L26 (-400.1, -384.5) -> (-400.1, -381.5) construction
  line L27 (-403, -384.5) -> (-403, -381.5)
  line L28 (-397.2, -381.5) -> (-397.2, -384.5)
  arc A10 (-403, -384.5) -> (-397.2, -384.5) centre (-400.1, -384.5) ccw
  arc A11 (-397.2, -381.5) -> (-403, -381.5) centre (-400.1, -381.5) ccw
  arc A12 (-403, -270.5) -> (-397.2, -270.5) centre (-400.1, -270.5) ccw
  line L29 (-403, -267.5) -> (-403, -270.5)
  line L30 (-400.1, -267.5) -> (-400.1, -270.5) construction
  line L31 (-397.2, -270.5) -> (-397.2, -267.5)
  arc A13 (-397.2, -267.5) -> (-403, -267.5) centre (-400.1, -267.5) ccw
  arc A14 (-411.5, -278.9) -> (-411.5, -273.1) centre (-411.5, -276) ccw
  line L32 (-411.5, -273.1) -> (-414.5, -273.1)
  line L33 (-414.5, -276) -> (-411.5, -276) construction
  line L34 (-414.5, -278.9) -> (-411.5, -278.9)
  arc A15 (-414.5, -273.1) -> (-414.5, -278.9) centre (-414.5, -276) ccw
  point P0 (0, 0)
  point P1 (191, -376)
  point P2 (178.1, -383)
  point P3 (191, -276)
  point P4 (178.1, -269)
  point P5 (-413, -376)
  point P6 (-400.1, -383)
  point P7 (-400.1, -269)
  point P8 (-413, -276)
  dimension "d571" = 5.8
  dimension "d572" = 8.5
  dimension "d573" = 3
  dimension "d574" = 20
  dimension "d575" = 3
  dimension "d576" = 5.8
  dimension "d577" = 8.5
  dimension "d578" = 20
  constraints: 68 end point, 42 symmetric about line, 32 point on circle, 16 centre point, 8 tangent, 5 midpoint, 2 parallel, 2 vertical, 1 horizontal, 1 point on line, 12 other
  measures "d571" diameter of A1
  measures "d572" distance from line of L3 L0.start
  measures "d573" distance of L0.start L0.end
  measures "d574" distance between parallel lines of L4 L0
  measures "d575" distance of L5.start L5.end
  measures "d576" diameter of A3
  measures "d577" distance from line of L8 L5.start
  measures "d578" distance between parallel lines of L3 L6
extrude "Extrusion14" [suppressed]
equation "\"d79\" = CylinderStroke"
equation "\"d81\" = SideAreaWidth"
equation "\"GridTotalSize\" = 63"
equation "\"DistanceBetweenGrid\" = 5"
equation "\"GridProcutClearance\" = 3"
equation "\"GridBorderThickness\" = 5"
equation "\"GridBorderFillets\" = 7"
equation "\"WorkspaceHeight\" = 183"
equation "\"AxesBaseFillet\" = 15"
equation "\"Zaxis\" = 197"
equation "\"ProductTotalHeight\" = 45"
equation "\"VerticalStroke\" = 105"
equation "\"CylinderStroke\" = 75"
equation "\"SideAreaWidth\" = 200"
equation "\"BaseWoodThickness\" = 7"
equation "\"kerf\" = 1.5"
equation "\"Kerf\" = 0.3"
equation "\"RxThickness\" = 1.8"
body "Solid1"
